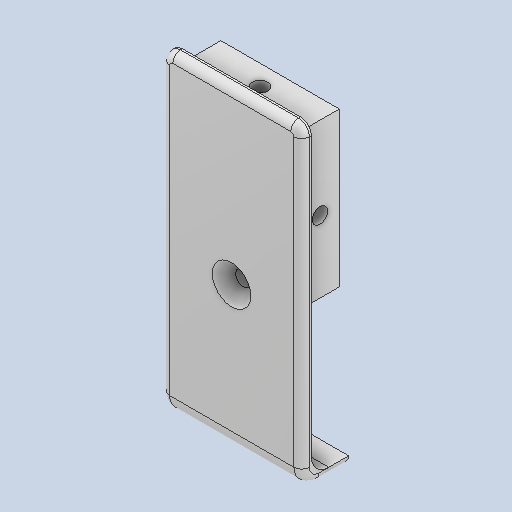
# Autodesk Inventor part: g
Saved by Autodesk Inventor 2025.2 (Build 292293000, 293)
## iProperties
Created: 2022-01-17
Part Number: g
Material: Aluminio
Document SubType Name: Modeling
Designer: Fabia
Density: 2.7 g/cm^3
Appearance: Satinado
Author: Fabia
Autodesk Inventor part; units mm, degrees
ref_plane "YZ Plane" through (0, 0, 0) normal (1, 0, 0) x (0, 1, 0)
ref_plane "XZ Plane" through (0, 0, 0) normal (0, 1, 0) x (-1, 0, 0)
ref_plane "XY Plane" through (0, 0, 0) normal (0, 0, 1) x (1, 0, 0)
sketch "Boceto1" plane through (0, 0, 0) normal (0, 0, 1) x (1, 0, 0)
  line L0 (-17.002, 0) -> (-17.002, 38.1)
  line L1 (-17.002, 0) -> (-16.004, 0)
  line L2 (-16.004, 0) -> (-16.004, 38.002)
  line L3 (-16.004, 38.002) -> (0, 38.002)
  line L4 (0, 0) -> (0, 38.002)
  line L5 (0.998, 0) -> (0, 0)
  line L6 (0.998, 38.1) -> (0.998, 0)
  line L7 (-16.004, 38.002) -> (0, 38.002)
  line L8 (0, 38.002) -> (0, 0)
  line L9 (0, 0) -> (-16.004, 0)
  line L10 (-16.004, 0) -> (-16.004, 38.002)
  circle A0 centre (-8.0204, 14.0333) radius 0.9761
  arc A1 (0.998, 38.1) -> (-0.402, 39.5) centre (-0.402, 38.1) ccw
  line L11 (-15.602, 39.5) -> (-0.402, 39.5)
  arc A2 (-15.602, 39.5) -> (-17.002, 38.1) centre (-15.602, 38.1) ccw
  constraints: 24 end point, 4 point on circle, 3 centre point
extrude "Extrusión1" add sketch "Boceto1" along normal blind 1.25
sketch "Boceto2" plane through (0, 0, 0) normal (0, 0, -1) x (-1, 0, 0)
  circle A0 centre (8.0204, 17.6043) radius 3.9493
  circle A1 centre (8.0204, 17.6043) radius 0.9761
  point P0 (0, 0)
  constraints: 2 centre point
extrude "Extrusión2" add sketch "Boceto2" along normal blind 2
sketch "Boceto3" plane through (-16.004, 0, 0) normal (0, -1, 0) x (1, 0, 0)
  line L0 (0, -4.8087) -> (16.004, -4.8087)
  line L1 (0, -4.8087) -> (0, 0)
  line L2 (-0.998, 0) -> (0, 0)
  line L3 (-0.998, 0) -> (-0.998, -19)
  line L4 (-0.998, -19) -> (17.002, -19)
  line L5 (17.002, -19) -> (17.002, 0)
  line L6 (17.002, 0) -> (16.004, 0)
  line L7 (16.004, -4.8087) -> (16.004, 0)
  line L8 (16.004, 1.25) -> (0, 1.25)
  line L9 (0, 1.25) -> (16.004, 1.25)
  line L10 (16.004, 1.25) -> (16.004, -4.8087)
  line L11 (0, -12.002) -> (0, 1.25)
  line L12 (0, -12.002) -> (16.004, -12.002)
  line L13 (0, -12.002) -> (0, 0)
  line L14 (-0.998, 0) -> (0, 0)
  line L15 (-0.998, 0) -> (-0.998, -19)
  line L16 (-0.998, -19) -> (17.002, -19)
  line L17 (17.002, -19) -> (17.002, 0)
  line L18 (17.002, 0) -> (16.004, 0)
  line L19 (16.004, -12.002) -> (16.004, 0)
  line L20 (0.402, 1.25) -> (-0.998, 1.25) projected
  line L21 (17.002, 0) -> (17.002, 1.25) projected
  line L22 (-0.998, 1.25) -> (17.002, 1.25)
  line L23 (17.002, 1.25) -> (17.002, 0)
  line L24 (17.002, 0) -> (-0.998, 0)
  line L25 (-0.998, 0) -> (-0.998, 1.25)
  line L26 (-0.998, 1.25) -> (17.002, 1.25)
  line L27 (17.002, 1.25) -> (17.002, -4.8087)
  line L28 (17.002, -4.8087) -> (-0.998, -4.8087)
  line L29 (-0.998, -4.8087) -> (-0.998, 1.25)
  constraints: 56 end point, 4 parallel, 2 horizontal, 2 perpendicular, 1 point on line
extrude "Extrusión3" add sketch "Boceto3" along normal blind 1 contours L1 L24 L7 L0 | L28 L3 L2 L1 | L7 L6 L5 L28 | L2 L25 L20 L11 | L11 L8 L10 L24 | L10 L22 L21 L6
fillet "Empalme1" radius 2.25 2 edges at (-8.002, -1, 1.25) (-8.002, 0, 0)
sketch "Boceto4" plane through (0, 0, 0) normal (0, 0, -1) x (-1, 0, 0)
  line L0 (15.6548, 18.0312) -> (15.6548, 37.8799)
  line L1 (15.6548, 37.8799) -> (0.4041, 37.8799)
  line L2 (0.4041, 18.0312) -> (0.4041, 37.8799)
  line L3 (1.7992, 18.0312) -> (1.7992, 36.4849)
  line L4 (1.7992, 36.4849) -> (14.2598, 36.4849)
  line L5 (14.2598, 36.4849) -> (14.2598, 18.0312)
  line L6 (-0.998, 1.25) -> (17.002, 1.25) projected
  line L7 (17.002, 38.1) -> (17.002, 1.25) projected
  line L8 (15.6548, 37.8799) -> (0.4041, 37.8799)
  line L9 (0.4041, 37.8799) -> (0.4041, 18.0312)
  line L10 (0.4041, 18.0312) -> (15.6548, 18.0312)
  line L11 (15.6548, 18.0312) -> (15.6548, 37.8799)
  point P0 (0, 0)
  constraints: 20 end point, 2 parallel, 2 point on line, 1 horizontal, 1 perpendicular
extrude "Extrusión4" add sketch "Boceto4" along normal blind 5 contours L10 L5 L4 L3 L2 L1 L0
sketch "Boceto5" plane through (-15.6548, 37.8799, 0) normal (0, 1, 0) x (1, 0, 0)
  line L0 (-4.5133, 5.6545) -> (19.8189, 5.6545)
  line L1 (7.6528, 5.6545) -> (7.6528, -0.8458)
  line L2 (17.9264, -0.8458) -> (-2.6208, -0.8458)
  circle A0 centre (7.6528, 2.4043) radius 1
  point P0 (18.4698, -0.8458)
  dimension "d18" = 2
  constraints: 6 end point, 3 midpoint, 1 centre point
  measures "d18" diameter of A0
extrude "Extrusión5" cut sketch "Boceto5" along normal mid plane 5
sketch "Boceto6" plane through (-15.6548, 18.0312, 0) normal (-1, 0, 0) x (0, 0, 1)
  line L0 (-5, 0) -> (-5, 18.4537) projected
  line L1 (-5, 9.2268) -> (0, 9.2268)
  line L2 (0, 18.4537) -> (0, 0) projected
  circle A0 centre (-2.5, 9.2268) radius 1
  point P0 (0, -18.0312)
  dimension "d14" = 2
  constraints: 3 midpoint, 2 end point, 1 centre point
  measures "d14" diameter of A0
extrude "Extrusión6" cut sketch "Boceto6" against normal blind 32.75
fillet "Empalme2" radius 1 9 edges at (0.998, -0.341, 0.591) (0.998, -1, -2.9043) (0.5879, 39.0899, 1.25) (-8.002, 39.5, 1.25) (-16.5919, 39.0899, 1.25) (-17.002, 19.675, 1.25) (-17.002, -0.341, 0.591) (-17.002, -1, -2.9043) (0.998, 19.675, 1.25)
sketch "Boceto7" plane through (0, 0, 0) normal (0, 0, -1) x (-1, 0, 0)
  circle A0 centre (8.0204, 17.6043) radius 0.9761 projected
  point P0 (0, 0)
extrude "Extrusión7" cut sketch "Boceto7" against normal blind 10
sketch "Boceto8" plane through (0, 0, 0) normal (0, 0, -1) x (-1, 0, 0)
  circle A0 centre (8.0204, 14.0333) radius 0.9761 projected
  point P0 (0, 0)
extrude "Extrusión8" add sketch "Boceto8" against normal up to surface (1.25 mm away)
chamfer "Chaflán1" distance 1.5 angle 45 1 edges at (-7.0444, 17.6043, 1.25)
